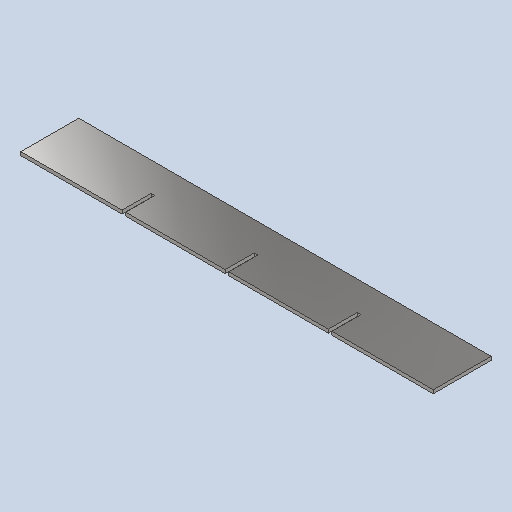
# Autodesk Inventor part: RDS-1207 Grate Strip Short
Saved by Autodesk Inventor 2026.2 (Build 302298000, 298)
## iProperties
Created: 2026-10-18
Part Number: RDS-1207 Grate Strip Short
Material: Stainless Steel, Austenitic
Description: Grate strip short, on edge, slots from top, AISI 304 3 mm
Document SubType Name: Sheet Metal
Designer: admin
Stock Number: Колосник поперечный 3 мм (×4)
Density: 8 g/cm^3
Flat Pattern Width: 5 cm
Flat Pattern Length: 35.6 cm
Flat Pattern Area: 178 cm^2
Sheet Metal Rule: Default
Sheet Metal Width: 50,000 mm
Sheet Metal Length: 356,000 mm
Sheet Metal Area: 17800,000 mm^2
Appearance: Semi-Polished
Author: admin
Autodesk Inventor part; units mm, degrees
ref_plane "YZ Plane" through (0, 0, 0) normal (1, 0, 0) x (0, 1, 0)
ref_plane "XZ Plane" through (0, 0, 0) normal (0, 1, 0) x (-1, 0, 0)
ref_plane "XY Plane" through (0, 0, 0) normal (0, 0, 1) x (1, 0, 0)
sketch "Sketch1" plane through (0, 0, 0) normal (0, 1, 0) x (-1, 0, 0)
  line L0 (178, -25) -> (-178, -25)
  line L1 (-178, -25) -> (-178, 25)
  line L2 (-178, 25) -> (178, 25)
  line L3 (178, 25) -> (178, -25)
  dimension "d0" = 356
  dimension "d1" = 50
  measures "d0" distance of L0.start L0.end
  measures "d1" distance of L0.end L1.end
extrude "Plate1" add sketch "Sketch1" along normal blind 3
sketch "Sketch2" plane through (0, 3, 0) normal (0, 1, 0) x (1, 0, 0)
  line L0 (-90.6, 0) -> (-87.4, 0)
  line L1 (-87.4, 0) -> (-87.4, -25)
  line L2 (-87.4, -25) -> (-90.6, -25)
  line L3 (-90.6, -25) -> (-90.6, 0)
  line L4 (-1.6, 0) -> (1.6, 0)
  line L5 (1.6, 0) -> (1.6, -25)
  line L6 (1.6, -25) -> (-1.6, -25)
  line L7 (-1.6, -25) -> (-1.6, 0)
  line L8 (87.4, 0) -> (90.6, 0)
  line L9 (90.6, 0) -> (90.6, -25)
  line L10 (90.6, -25) -> (87.4, -25)
  line L11 (87.4, -25) -> (87.4, 0)
  constraints: 24 end point, 6 parallel, 3 horizontal, 3 perpendicular
extrude "Cut1" cut sketch "Sketch2" against normal blind 3
equation "\"d0\" = Grate1207_Width"
equation "\"d1\" = Grate1207_Length"
equation "\"d2\" = Thickness"
equation "\"BendRadius\" = Thickness"
equation "\"BendReliefWidth\" = Thickness"
equation "\"BendReliefDepth\" = 0.5 * Thickness"
equation "\"CornerReliefSize\" = 4 * Thickness"
equation "\"MinimumRemnant\" = 2 * Thickness"
equation "\"TransitionRadius\" = BendRadius"
equation "\"JacobiRadiusSize\" = BendRadius"
equation "\"GapSize\" = Thickness"
equation "\"Grate1207_Width\" = 356"
equation "\"Grate1207_Length\" = 50"
equation "\"Thickness\" = 3"
body "Solid1"
